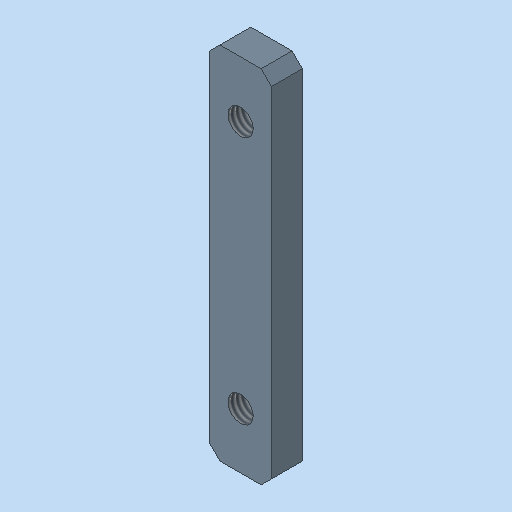
# Autodesk Inventor part: MM0948AN100_G01_121
Saved by Autodesk Inventor 2023.3 (Build 273359000, 359)
## iProperties
Created: 2023-03-23
Part Number: MM0948AN100_G01_121
Material: 1.0330 DC01
Description: =<RBPARTNOTITLE2>
Document SubType Name: Blech
Designer: ric7an
Mass: 4.67472 g
Surface Area: 6.82325 cm^2
Volume: 0.595506 cm^3
Density: 7.85 g/cm^3
Sheet Metal Rule: Standard_mm
Appearance: Stahl - kein Standard AnP(1)
AnP_Kategorie: 1
AnP_Material: =<Material>
MaxAbmaße: 3 x 35 x 6 (FM)
AnP_TemplVers: 20200821
RBDOCUMENTTYPE: DRF
RBDOCUMENTVERSION: 00
RBDRAWINGMAINSCALE: 1:1
RBDRAWINGMISSINGSPEC: --
RBDRAWINGVOLUME: --
RBDSV1: 0850
RBGBEDGESIN1: +0,5
RBGBEDGESIN2: +0,2
RBGBEDGESOUT1: -0,3
RBGBEDGESOUT2: -0,1
RBMATERIAL: =<Material>
RBMATMEETS: --
RBMATNO: =<Part Number>
RBPARTMADEOF: 3 x 35 x 6 (FM)
RBPARTNO: SIEHE MNR
RBPARTNOTITLE1: manufactured part
RBPARTNOTITLE2: Anfertigungsteil
RBPARTSAFETYINDICATOR: --
RBSURFACE: --
RBSURFACE2: --
RBZEDGESNORM: ISO13715:2002-06
RBZGENDIMCLASS: m
RBZGENDIMNORM: ISO 2768-1:1989-11
RBZGENGEOCLASS: H
RBZGENGEONORM: ISO 2768-2:1989-11
RBZSURFACENORM: ISO13D2:2002-02
RBZTOLERANCENORM: ISO 14405-1:2010-12
AnP_Kommentar_aktuell: =<Comments>
AnP_Material_aktuell: =<Material>
Author: FH/Wi
Keywords: =<RBPARTMADEOF>
Comments: =<RBSURFACE2>
Revision Number: 01
Autodesk Inventor part; units mm, degrees
ref_plane "YZ Plane" through (0, 0, 0) normal (1, 0, 0) x (0, 1, 0)
ref_plane "XZ Plane" through (0, 0, 0) normal (0, 1, 0) x (-1, 0, 0)
ref_plane "XY Plane" through (0, 0, 0) normal (0, 0, 1) x (1, 0, 0)
sketch "Skizze1" plane through (0, 0, 0) normal (0, 0, 1) x (1, 0, 0)
  line L0 (-3, 17.5) -> (3, 17.5)
  line L1 (3, 17.5) -> (3, -17.5)
  line L2 (3, -17.5) -> (-3, -17.5)
  line L3 (-3, -17.5) -> (-3, 17.5)
  line L4 (-4.2, 0) -> (4.2, 0)
  line L5 (0, 24.5) -> (0, -24.5)
  point P0 (0, 0)
  dimension "d0" = 6
  dimension "d1" = 35
  measures "d0" distance of L0.start L0.end
  measures "d1" distance of L2.end L0.start
extrude "Grobblech1" add sketch "Skizze1" along normal blind 3
sketch "Skizze2" plane through (0, 0, 3) normal (0, 0, 1) x (1, 0, 0)
  line L0 (0, 24.5) -> (0, -24.5) projected
  line L1 (-4.2, 0) -> (4.2, 0) projected
  line L2 (3, -17.5) -> (-3, -17.5) projected
  point P0 (0, 0)
  point P1 (0, 12.05)
  point P2 (0, -12.1)
  dimension "d3" = 24.15
  dimension "d14" = 5.4
  constraints: 1 point on line
  measures "d3" distance of point (0, -12.1) point (0, 12.05)
  measures "d14" distance from line of L2 point (0, -12.1)
hole "Bohrung1" at (0, 12.05, 3) at (0, -12.1, 3) direction (0, 0, -1) diameter 2.459 end through all thread size "M3x0.5" designation "M3" class "6H" standard "ISO Metric profile"
chamfer "Eckenfase1" distance 1 angle 45 4 edges at (-3, 17.5, 1.5) (3, 17.5, 1.5) (3, -17.5, 1.5) (-3, -17.5, 1.5)
equation "\"d2\" = Stärke"
equation "\"Biegeradius\" = Stärke"
equation "\"BreiteBiegungsfreistellung\" = Stärke"
equation "\"TiefeBiegungsfreistellung\" = 0.5 * Stärke"
equation "\"GrößeEckenfreistellung\" = 4 * Stärke"
equation "\"MinimalRest\" = 2 * Stärke"
equation "\"Übergangsradius\" = Biegeradius"
equation "\"JacobiRadiusGröße\" = Biegeradius"
equation "\"Abstandsgröße\" = Stärke"
equation "\"Stärke\" = 3"
